210201_P01_WALL-PANEL-ASSY-BACK-LOWER-B1_CAD (Autodesk Fusion 360 design; units mm, degrees)
description: WALL - PANEL ASSY - BACK LOWER - B1 | Vách hậu - cụm tấm dưới trái | P01 | position B1
part number: 210201
description: WALL - PANEL FRAME - BACK LOWER - B1 | Vách hậu - khung dưới trái | P01
part number: 211201
description: WALL - SKIN - BACK LOWER - B1 | Vách hậu - tấm ốp alu dưới trái | P01
part number: 211401
description: WALL - CAVITY FILL - BACK LOWER - B1 | Vách hậu - bông PET dưới trái | P01
part number: 211601
description: HARDWARE - STOP WASHER - Ø10.5 X Ø20 X 1.5 - AL | Long đen chặn nhôm | P01
part number: 831002
description: HARDWARE - RIVET NUT - M6 - SHEREX CAH3-610-4.2 | Tán rút M6 | P01
part number: 838003
description: HARDWARE - LOCATING SPIGOT - M6 X Ø8 - STAINLESS | Chốt định vị Ø8 | P01
part number: 831001
Autodesk Fusion 360 part; units mm, degrees
(part 1 of 2)
ref_plane "WorkPlane1" through (0, 0, 112.26) normal (0, 0, 1) x (1, 0, 0) in component "211201 WALL - PANEL FRAME - BACK LOWER - B1"
sketch "SKETCH - RAIL - BOTTOM TUBE" plane through (0, 0, 112.26) normal (0, 0, 1) x (1, 0, 0) in component "211201 WALL - PANEL FRAME - BACK LOWER - B1"
  line L0 (-1201.74, 804) -> (-2.75, 804)
  line L1 (-2.75, 804) -> (-2.75, 844)
  line L2 (-2.75, 844) -> (-1201.74, 844)
  line L3 (-1201.74, 844) -> (-1201.74, 804)
  dimension "d679" = 1198.99
  dimension "d680" = 40
  dimension "d681" = 1201.74
  dimension "d682" = 804
  constraint horizontal L0
  constraint vertical L1
  constraint horizontal L2
  constraint vertical L3
  measures "d679" horizontal distance of L0.start L0.end
  measures "d680" vertical distance of L0.start L2.end
  measures "d681" horizontal distance of origin L0.start
  measures "d682" vertical distance of origin L0.start
extrude "EXTRUDE - RAIL - BOTTOM TUBE" add sketch "SKETCH - RAIL - BOTTOM TUBE" along normal blind 20 makes body 1 in component "211201 WALL - PANEL FRAME - BACK LOWER - B1"
ref_plane "WorkPlane2" through (0, 0, 113.46) normal (0, 0, 1) x (1, 0, 0) in component "211201 WALL - PANEL FRAME - BACK LOWER - B1"
sketch "SKETCH - RAIL - BOTTOM BORE" plane through (0, 0, 113.46) normal (0, 0, 1) x (1, 0, 0) in component "211201 WALL - PANEL FRAME - BACK LOWER - B1"
  line L0 (-1201.74, 805.2) -> (-2.75, 805.2)
  line L1 (-2.75, 805.2) -> (-2.75, 842.8)
  line L2 (-2.75, 842.8) -> (-1201.74, 842.8)
  line L3 (-1201.74, 842.8) -> (-1201.74, 805.2)
  dimension "d687" = 1198.99
  dimension "d688" = 37.6
  dimension "d689" = 1201.74
  dimension "d690" = 805.2
  constraint horizontal L0
  constraint vertical L1
  constraint horizontal L2
  constraint vertical L3
  measures "d687" horizontal distance of L0.start L0.end
  measures "d688" vertical distance of L0.start L2.end
  measures "d689" horizontal distance of origin L0.start
  measures "d690" vertical distance of origin L0.start
extrude "CUT - RAIL - BOTTOM BORE" cut sketch "SKETCH - RAIL - BOTTOM BORE" along normal blind 17.6 bodies 1 in component "211201 WALL - PANEL FRAME - BACK LOWER - B1"
ref_plane "WorkPlane3" through (0, 0, 1210.87) normal (0, 0, 1) x (1, 0, 0) in component "211201 WALL - PANEL FRAME - BACK LOWER - B1"
sketch "SKETCH - RAIL - TOP TUBE" plane through (0, 0, 1210.87) normal (0, 0, 1) x (1, 0, 0) in component "211201 WALL - PANEL FRAME - BACK LOWER - B1"
  line L0 (-1201.74, 804) -> (-2.75, 804)
  line L1 (-2.75, 804) -> (-2.75, 844)
  line L2 (-2.75, 844) -> (-1201.74, 844)
  line L3 (-1201.74, 844) -> (-1201.74, 804)
  dimension "d695" = 1198.99
  dimension "d696" = 40
  dimension "d697" = 1201.74
  dimension "d698" = 804
  constraint horizontal L0
  constraint vertical L1
  constraint horizontal L2
  constraint vertical L3
  measures "d695" horizontal distance of L0.start L0.end
  measures "d696" vertical distance of L0.start L2.end
  measures "d697" horizontal distance of origin L0.start
  measures "d698" vertical distance of origin L0.start
extrude "EXTRUDE - RAIL - TOP TUBE" add sketch "SKETCH - RAIL - TOP TUBE" along normal blind 20 separate body makes body 2 in component "211201 WALL - PANEL FRAME - BACK LOWER - B1"
ref_plane "WorkPlane4" through (0, 0, 1212.07) normal (0, 0, 1) x (1, 0, 0) in component "211201 WALL - PANEL FRAME - BACK LOWER - B1"
sketch "SKETCH - RAIL - TOP BORE" plane through (0, 0, 1212.07) normal (0, 0, 1) x (1, 0, 0) in component "211201 WALL - PANEL FRAME - BACK LOWER - B1"
  line L0 (-1201.74, 805.2) -> (-2.75, 805.2)
  line L1 (-2.75, 805.2) -> (-2.75, 842.8)
  line L2 (-2.75, 842.8) -> (-1201.74, 842.8)
  line L3 (-1201.74, 842.8) -> (-1201.74, 805.2)
  dimension "d703" = 1198.99
  dimension "d704" = 37.6
  dimension "d705" = 1201.74
  dimension "d706" = 805.2
  constraint horizontal L0
  constraint vertical L1
  constraint horizontal L2
  constraint vertical L3
  measures "d703" horizontal distance of L0.start L0.end
  measures "d704" vertical distance of L0.start L2.end
  measures "d705" horizontal distance of origin L0.start
  measures "d706" vertical distance of origin L0.start
extrude "CUT - RAIL - TOP BORE" cut sketch "SKETCH - RAIL - TOP BORE" along normal blind 17.6 bodies 2 in component "211201 WALL - PANEL FRAME - BACK LOWER - B1"
ref_plane "WorkPlane5" through (0, 0, 132.26) normal (0, 0, 1) x (1, 0, 0) in component "211201 WALL - PANEL FRAME - BACK LOWER - B1"
sketch "SKETCH - STILE - OUTER TUBE" plane through (0, 0, 132.26) normal (0, 0, 1) x (1, 0, 0) in component "211201 WALL - PANEL FRAME - BACK LOWER - B1"
  line L0 (-1201.74, 804) -> (-1181.74, 804)
  line L1 (-1181.74, 804) -> (-1181.74, 844)
  line L2 (-1181.74, 844) -> (-1201.74, 844)
  line L3 (-1201.74, 844) -> (-1201.74, 804)
  dimension "d711" = 20
  dimension "d712" = 40
  dimension "d713" = 1201.74
  dimension "d714" = 804
  constraint horizontal L0
  constraint vertical L1
  constraint horizontal L2
  constraint vertical L3
  measures "d711" horizontal distance of L0.start L0.end
  measures "d712" vertical distance of L0.start L2.end
  measures "d713" horizontal distance of origin L0.start
  measures "d714" vertical distance of origin L0.start
extrude "EXTRUDE - STILE - OUTER TUBE" add sketch "SKETCH - STILE - OUTER TUBE" along normal blind 1078.61 separate body makes body 3 in component "211201 WALL - PANEL FRAME - BACK LOWER - B1"
ref_plane "WorkPlane6" through (0, 0, 132.26) normal (0, 0, 1) x (1, 0, 0) in component "211201 WALL - PANEL FRAME - BACK LOWER - B1"
sketch "SKETCH - STILE - OUTER BORE" plane through (0, 0, 132.26) normal (0, 0, 1) x (1, 0, 0) in component "211201 WALL - PANEL FRAME - BACK LOWER - B1"
  line L0 (-1200.54, 805.2) -> (-1182.94, 805.2)
  line L1 (-1182.94, 805.2) -> (-1182.94, 842.8)
  line L2 (-1182.94, 842.8) -> (-1200.54, 842.8)
  line L3 (-1200.54, 842.8) -> (-1200.54, 805.2)
  dimension "d719" = 17.6
  dimension "d720" = 37.6
  dimension "d721" = 1200.54
  dimension "d722" = 805.2
  constraint horizontal L0
  constraint vertical L1
  constraint horizontal L2
  constraint vertical L3
  measures "d719" horizontal distance of L0.start L0.end
  measures "d720" vertical distance of L0.start L2.end
  measures "d721" horizontal distance of origin L0.start
  measures "d722" vertical distance of origin L0.start
extrude "CUT - STILE - OUTER BORE" cut sketch "SKETCH - STILE - OUTER BORE" along normal blind 1078.61 bodies 3 in component "211201 WALL - PANEL FRAME - BACK LOWER - B1"
ref_plane "WorkPlane7" through (0, 0, 132.26) normal (0, 0, 1) x (1, 0, 0) in component "211201 WALL - PANEL FRAME - BACK LOWER - B1"
sketch "SKETCH - STILE - CENTRE TUBE" plane through (0, 0, 132.26) normal (0, 0, 1) x (1, 0, 0) in component "211201 WALL - PANEL FRAME - BACK LOWER - B1"
  line L0 (-22.75, 804) -> (-2.75, 804)
  line L1 (-2.75, 804) -> (-2.75, 844)
  line L2 (-2.75, 844) -> (-22.75, 844)
  line L3 (-22.75, 844) -> (-22.75, 804)
  dimension "d727" = 20
  dimension "d728" = 40
  dimension "d729" = 22.75
  dimension "d730" = 804
  constraint horizontal L0
  constraint vertical L1
  constraint horizontal L2
  constraint vertical L3
  measures "d727" horizontal distance of L0.start L0.end
  measures "d728" vertical distance of L0.start L2.end
  measures "d729" horizontal distance of origin L0.start
  measures "d730" vertical distance of origin L0.start
extrude "EXTRUDE - STILE - CENTRE TUBE" add sketch "SKETCH - STILE - CENTRE TUBE" along normal blind 1078.61 separate body makes body 4 in component "211201 WALL - PANEL FRAME - BACK LOWER - B1"
ref_plane "WorkPlane8" through (0, 0, 132.26) normal (0, 0, 1) x (1, 0, 0) in component "211201 WALL - PANEL FRAME - BACK LOWER - B1"
sketch "SKETCH - STILE - CENTRE BORE" plane through (0, 0, 132.26) normal (0, 0, 1) x (1, 0, 0) in component "211201 WALL - PANEL FRAME - BACK LOWER - B1"
  line L0 (-21.55, 805.2) -> (-3.95, 805.2)
  line L1 (-3.95, 805.2) -> (-3.95, 842.8)
  line L2 (-3.95, 842.8) -> (-21.55, 842.8)
  line L3 (-21.55, 842.8) -> (-21.55, 805.2)
  dimension "d735" = 17.6
  dimension "d736" = 37.6
  dimension "d737" = 21.55
  dimension "d738" = 805.2
  constraint horizontal L0
  constraint vertical L1
  constraint horizontal L2
  constraint vertical L3
  measures "d735" horizontal distance of L0.start L0.end
  measures "d736" vertical distance of L0.start L2.end
  measures "d737" horizontal distance of origin L0.start
  measures "d738" vertical distance of origin L0.start
extrude "CUT - STILE - CENTRE BORE" cut sketch "SKETCH - STILE - CENTRE BORE" along normal blind 1078.61 bodies 4 in component "211201 WALL - PANEL FRAME - BACK LOWER - B1"
ref_plane "WorkPlane9" through (0, 0, 132.26) normal (0, 0, 1) x (1, 0, 0) in component "211201 WALL - PANEL FRAME - BACK LOWER - B1"
sketch "SKETCH - STILE - MID 1 TUBE" plane through (0, 0, 132.26) normal (0, 0, 1) x (1, 0, 0) in component "211201 WALL - PANEL FRAME - BACK LOWER - B1"
  line L0 (-808.7433, 804) -> (-788.7433, 804)
  line L1 (-788.7433, 804) -> (-788.7433, 844)
  line L2 (-788.7433, 844) -> (-808.7433, 844)
  line L3 (-808.7433, 844) -> (-808.7433, 804)
  dimension "d743" = 20
  dimension "d744" = 40
  dimension "d745" = 808.7433
  dimension "d746" = 804
  constraint horizontal L0
  constraint vertical L1
  constraint horizontal L2
  constraint vertical L3
  measures "d743" horizontal distance of L0.start L0.end
  measures "d744" vertical distance of L0.start L2.end
  measures "d745" horizontal distance of origin L0.start
  measures "d746" vertical distance of origin L0.start
extrude "EXTRUDE - STILE - MID 1 TUBE" add sketch "SKETCH - STILE - MID 1 TUBE" along normal blind 1078.61 separate body makes body 5 in component "211201 WALL - PANEL FRAME - BACK LOWER - B1"
ref_plane "WorkPlane10" through (0, 0, 132.26) normal (0, 0, 1) x (1, 0, 0) in component "211201 WALL - PANEL FRAME - BACK LOWER - B1"
sketch "SKETCH - STILE - MID 1 BORE" plane through (0, 0, 132.26) normal (0, 0, 1) x (1, 0, 0) in component "211201 WALL - PANEL FRAME - BACK LOWER - B1"
  line L0 (-807.7433, 805) -> (-789.7433, 805)
  line L1 (-789.7433, 805) -> (-789.7433, 843)
  line L2 (-789.7433, 843) -> (-807.7433, 843)
  line L3 (-807.7433, 843) -> (-807.7433, 805)
  dimension "d751" = 18
  dimension "d752" = 38
  dimension "d753" = 807.7433
  dimension "d754" = 805
  constraint horizontal L0
  constraint vertical L1
  constraint horizontal L2
  constraint vertical L3
  measures "d751" horizontal distance of L0.start L0.end
  measures "d752" vertical distance of L0.start L2.end
  measures "d753" horizontal distance of origin L0.start
  measures "d754" vertical distance of origin L0.start
extrude "CUT - STILE - MID 1 BORE" cut sketch "SKETCH - STILE - MID 1 BORE" along normal blind 1078.61 bodies 5 in component "211201 WALL - PANEL FRAME - BACK LOWER - B1"
pattern_linear "PATTERN - STILES - MID" count 2 spacing 392.9967 along (1, 0, 0) of bodies 5 makes body 6 in component "211201 WALL - PANEL FRAME - BACK LOWER - B1"
ref_plane "WorkPlane1" through (0, 0, 112.26) normal (0, 0, 1) x (1, 0, 0) in component "211401 WALL - SKIN - BACK LOWER - B1"
sketch "SKETCH - SKIN PLATE" plane through (0, 0, 112.26) normal (0, 0, 1) x (1, 0, 0) in component "211401 WALL - SKIN - BACK LOWER - B1"
  line L0 (-1201.74, 847) -> (-1.13, 847)
  line L1 (-1.13, 847) -> (-1.13, 850)
  line L2 (-1.13, 850) -> (-1201.74, 850)
  line L3 (-1201.74, 850) -> (-1201.74, 847)
  dimension "d763" = 1200.61
  dimension "d764" = 3
  dimension "d765" = 1201.74
  dimension "d766" = 847
  constraint horizontal L0
  constraint vertical L1
  constraint horizontal L2
  constraint vertical L3
  measures "d763" horizontal distance of L0.start L0.end
  measures "d764" vertical distance of L0.start L2.end
  measures "d765" horizontal distance of origin L0.start
  measures "d766" vertical distance of origin L0.start
extrude "EXTRUDE - SKIN PLATE" add sketch "SKETCH - SKIN PLATE" along normal blind 1118.61 separate body makes body 7 in component "211401 WALL - SKIN - BACK LOWER - B1"
ref_plane "WorkPlane1" through (0, 0, 132.26) normal (0, 0, 1) x (1, 0, 0) in component "211601 WALL - CAVITY FILL - BACK LOWER - B1"
sketch "SKETCH - FILL BAY 1" plane through (0, 0, 132.26) normal (0, 0, 1) x (1, 0, 0) in component "211601 WALL - CAVITY FILL - BACK LOWER - B1"
  line L0 (-1181.74, 804) -> (-808.7433, 804)
  line L1 (-808.7433, 804) -> (-808.7433, 844)
  line L2 (-808.7433, 844) -> (-1181.74, 844)
  line L3 (-1181.74, 844) -> (-1181.74, 804)
  dimension "d771" = 372.9967
  dimension "d772" = 40
  dimension "d773" = 1181.74
  dimension "d774" = 804
  constraint horizontal L0
  constraint vertical L1
  constraint horizontal L2
  constraint vertical L3
  measures "d771" horizontal distance of L0.start L0.end
  measures "d772" vertical distance of L0.start L2.end
  measures "d773" horizontal distance of origin L0.start
  measures "d774" vertical distance of origin L0.start
extrude "EXTRUDE - FILL BAY 1" add sketch "SKETCH - FILL BAY 1" along normal blind 1078.61 separate body makes body 8 in component "211601 WALL - CAVITY FILL - BACK LOWER - B1"
pattern_linear "PATTERN - FILL BAYS" count 3 spacing 392.9967 along (1, 0, 0) of bodies 8 makes body 9 at (-540.0789, 844, 851.3333) makes body 10 at (-147.0822, 844, 491.7967) in component "211601 WALL - CAVITY FILL - BACK LOWER - B1"
ref_plane "WorkPlane2" through (0, 0, 132.26) normal (0, 0, 1) x (1, 0, 0) in component "211601 WALL - CAVITY FILL - BACK LOWER - B1"
sketch "SKETCH - FILL POCKET BOTTOM BOLT 1" plane through (0, 0, 132.26) normal (0, 0, 1) x (1, 0, 0) in component "211601 WALL - CAVITY FILL - BACK LOWER - B1"
  line L0 (-1011.74, 804) -> (-951.74, 804)
  line L1 (-951.74, 804) -> (-951.74, 844)
  line L2 (-951.74, 844) -> (-1011.74, 844)
  line L3 (-1011.74, 844) -> (-1011.74, 804)
  dimension "d783" = 60
  dimension "d784" = 40
  dimension "d785" = 1011.74
  dimension "d786" = 804
  constraint horizontal L0
  constraint vertical L1
  constraint horizontal L2
  constraint vertical L3
  measures "d783" horizontal distance of L0.start L0.end
  measures "d784" vertical distance of L0.start L2.end
  measures "d785" horizontal distance of origin L0.start
  measures "d786" vertical distance of origin L0.start
extrude "CUT - FILL POCKET BOTTOM BOLT 1" cut sketch "SKETCH - FILL POCKET BOTTOM BOLT 1" along normal blind 60 bodies 8 in component "211601 WALL - CAVITY FILL - BACK LOWER - B1"
ref_plane "WorkPlane3" through (0, 0, 132.26) normal (0, 0, 1) x (1, 0, 0) in component "211601 WALL - CAVITY FILL - BACK LOWER - B1"
sketch "SKETCH - FILL POCKET BOTTOM BOLT 2" plane through (0, 0, 132.26) normal (0, 0, 1) x (1, 0, 0) in component "211601 WALL - CAVITY FILL - BACK LOWER - B1"
  line L0 (-758.7433, 804) -> (-698.7433, 804)
  line L1 (-698.7433, 804) -> (-698.7433, 844)
  line L2 (-698.7433, 844) -> (-758.7433, 844)
  line L3 (-758.7433, 844) -> (-758.7433, 804)
  dimension "d791" = 60
  dimension "d792" = 40
  dimension "d793" = 758.7433
  dimension "d794" = 804
  constraint horizontal L0
  constraint vertical L1
  constraint horizontal L2
  constraint vertical L3
  measures "d791" horizontal distance of L0.start L0.end
  measures "d792" vertical distance of L0.start L2.end
  measures "d793" horizontal distance of origin L0.start
  measures "d794" vertical distance of origin L0.start
extrude "CUT - FILL POCKET BOTTOM BOLT 2" cut sketch "SKETCH - FILL POCKET BOTTOM BOLT 2" along normal blind 60 bodies 9 in component "211601 WALL - CAVITY FILL - BACK LOWER - B1"
ref_plane "WorkPlane4" through (0, 0, 132.26) normal (0, 0, 1) x (1, 0, 0) in component "211601 WALL - CAVITY FILL - BACK LOWER - B1"
sketch "SKETCH - FILL POCKET BOTTOM BOLT 3" plane through (0, 0, 132.26) normal (0, 0, 1) x (1, 0, 0) in component "211601 WALL - CAVITY FILL - BACK LOWER - B1"
  line L0 (-505.7467, 804) -> (-445.7467, 804)
  line L1 (-445.7467, 804) -> (-445.7467, 844)
  line L2 (-445.7467, 844) -> (-505.7467, 844)
  line L3 (-505.7467, 844) -> (-505.7467, 804)
  dimension "d799" = 60
  dimension "d800" = 40
  dimension "d801" = 505.7467
  dimension "d802" = 804
  constraint horizontal L0
  constraint vertical L1
  constraint horizontal L2
  constraint vertical L3
  measures "d799" horizontal distance of L0.start L0.end
  measures "d800" vertical distance of L0.start L2.end
  measures "d801" horizontal distance of origin L0.start
  measures "d802" vertical distance of origin L0.start
extrude "CUT - FILL POCKET BOTTOM BOLT 3" cut sketch "SKETCH - FILL POCKET BOTTOM BOLT 3" along normal blind 60 bodies 9 in component "211601 WALL - CAVITY FILL - BACK LOWER - B1"
ref_plane "WorkPlane5" through (0, 0, 132.26) normal (0, 0, 1) x (1, 0, 0) in component "211601 WALL - CAVITY FILL - BACK LOWER - B1"
sketch "SKETCH - FILL POCKET BOTTOM BOLT 4" plane through (0, 0, 132.26) normal (0, 0, 1) x (1, 0, 0) in component "211601 WALL - CAVITY FILL - BACK LOWER - B1"
  line L0 (-252.75, 804) -> (-192.75, 804)
  line L1 (-192.75, 804) -> (-192.75, 844)
  line L2 (-192.75, 844) -> (-252.75, 844)
  line L3 (-252.75, 844) -> (-252.75, 804)
  dimension "d807" = 60
  dimension "d808" = 40
  dimension "d809" = 252.75
  dimension "d810" = 804
  constraint horizontal L0
  constraint vertical L1
  constraint horizontal L2
  constraint vertical L3
  measures "d807" horizontal distance of L0.start L0.end
  measures "d808" vertical distance of L0.start L2.end
  measures "d809" horizontal distance of origin L0.start
  measures "d810" vertical distance of origin L0.start
extrude "CUT - FILL POCKET BOTTOM BOLT 4" cut sketch "SKETCH - FILL POCKET BOTTOM BOLT 4" along normal blind 60 bodies 10 in component "211601 WALL - CAVITY FILL - BACK LOWER - B1"
ref_plane "WorkPlane6" through (0, 0, 302.26) normal (0, 0, 1) x (1, 0, 0) in component "211601 WALL - CAVITY FILL - BACK LOWER - B1"
sketch "SKETCH - FILL POCKET CORNER BOLT 1" plane through (0, 0, 302.26) normal (0, 0, 1) x (1, 0, 0) in component "211601 WALL - CAVITY FILL - BACK LOWER - B1"
  line L0 (-1181.74, 804) -> (-1121.74, 804)
  line L1 (-1121.74, 804) -> (-1121.74, 844)
  line L2 (-1121.74, 844) -> (-1181.74, 844)
  line L3 (-1181.74, 844) -> (-1181.74, 804)
  dimension "d815" = 60
  dimension "d816" = 40
  dimension "d817" = 1181.74
  dimension "d818" = 804
  constraint horizontal L0
  constraint vertical L1
  constraint horizontal L2
  constraint vertical L3
  measures "d815" horizontal distance of L0.start L0.end
  measures "d816" vertical distance of L0.start L2.end
  measures "d817" horizontal distance of origin L0.start
  measures "d818" vertical distance of origin L0.start
extrude "CUT - FILL POCKET CORNER BOLT 1" cut sketch "SKETCH - FILL POCKET CORNER BOLT 1" along normal blind 60 bodies 8 in component "211601 WALL - CAVITY FILL - BACK LOWER - B1"
ref_plane "WorkPlane7" through (0, 0, 641.565) normal (0, 0, 1) x (1, 0, 0) in component "211601 WALL - CAVITY FILL - BACK LOWER - B1"
sketch "SKETCH - FILL POCKET CORNER BOLT 2" plane through (0, 0, 641.565) normal (0, 0, 1) x (1, 0, 0) in component "211601 WALL - CAVITY FILL - BACK LOWER - B1"
  line L0 (-1181.74, 804) -> (-1121.74, 804)
  line L1 (-1121.74, 804) -> (-1121.74, 844)
  line L2 (-1121.74, 844) -> (-1181.74, 844)
  line L3 (-1181.74, 844) -> (-1181.74, 804)
  dimension "d823" = 60
  dimension "d824" = 40
  dimension "d825" = 1181.74
  dimension "d826" = 804
  constraint horizontal L0
  constraint vertical L1
  constraint horizontal L2
  constraint vertical L3
  measures "d823" horizontal distance of L0.start L0.end
  measures "d824" vertical distance of L0.start L2.end
  measures "d825" horizontal distance of origin L0.start
  measures "d826" vertical distance of origin L0.start
extrude "CUT - FILL POCKET CORNER BOLT 2" cut sketch "SKETCH - FILL POCKET CORNER BOLT 2" along normal blind 60 bodies 8 in component "211601 WALL - CAVITY FILL - BACK LOWER - B1"
ref_plane "WorkPlane8" through (0, 0, 980.87) normal (0, 0, 1) x (1, 0, 0) in component "211601 WALL - CAVITY FILL - BACK LOWER - B1"
sketch "SKETCH - FILL POCKET CORNER BOLT 3" plane through (0, 0, 980.87) normal (0, 0, 1) x (1, 0, 0) in component "211601 WALL - CAVITY FILL - BACK LOWER - B1"
  line L0 (-1181.74, 804) -> (-1121.74, 804)
  line L1 (-1121.74, 804) -> (-1121.74, 844)
  line L2 (-1121.74, 844) -> (-1181.74, 844)
  line L3 (-1181.74, 844) -> (-1181.74, 804)
  dimension "d831" = 60
  dimension "d832" = 40
  dimension "d833" = 1181.74
  dimension "d834" = 804
  constraint horizontal L0
  constraint vertical L1
  constraint horizontal L2
  constraint vertical L3
  measures "d831" horizontal distance of L0.start L0.end
  measures "d832" vertical distance of L0.start L2.end
  measures "d833" horizontal distance of origin L0.start
  measures "d834" vertical distance of origin L0.start
extrude "CUT - FILL POCKET CORNER BOLT 3" cut sketch "SKETCH - FILL POCKET CORNER BOLT 3" along normal blind 60 bodies 8 in component "211601 WALL - CAVITY FILL - BACK LOWER - B1"
ref_plane "WorkPlane11" through (0, 0, 112.26) normal (0, 0, 1) x (1, 0, 0) in component "211201 WALL - PANEL FRAME - BACK LOWER - B1"
sketch "HOLE CENTRE - BOTTOM RAIL BOLT CLEARANCE 1" plane through (0, 0, 112.26) normal (0, 0, 1) x (1, 0, 0) in component "211201 WALL - PANEL FRAME - BACK LOWER - B1"
  point P0 (-981.74, 824)
  dimension "d839" = 981.74
  dimension "d840" = 824
  measures "d839" horizontal distance of origin P0
  measures "d840" vertical distance of origin P0
hole "HOLE - BOTTOM RAIL BOLT CLEARANCE 1" at (-981.74, 824, 112.26) direction (0, 0, 1) diameter 7 depth 1.2 tip angle 118 bodies 1 in component "211201 WALL - PANEL FRAME - BACK LOWER - B1"
ref_plane "WorkPlane12" through (0, 0, 132.26) normal (0, 0, 1) x (1, 0, 0) in component "211201 WALL - PANEL FRAME - BACK LOWER - B1"
sketch "HOLE CENTRE - BOTTOM RAIL KEY ACCESS 1" plane through (0, 0, 132.26) normal (0, 0, 1) x (1, 0, 0) in component "211201 WALL - PANEL FRAME - BACK LOWER - B1"
  point P0 (-981.74, 824)
  dimension "d846" = 981.74
  dimension "d847" = 824
  measures "d846" horizontal distance of origin P0
  measures "d847" vertical distance of origin P0
hole "HOLE - BOTTOM RAIL KEY ACCESS 1" at (-981.74, 824, 132.26) direction (0, 0, -1) diameter 19 depth 1.2 tip angle 118 bodies 1 in component "211201 WALL - PANEL FRAME - BACK LOWER - B1"
pattern_linear "PATTERN - BOTTOM RAIL BOLT HOLES" count 4 spacing 252.9967 along (1, 0, 0) of "HOLE - BOTTOM RAIL BOLT CLEARANCE 1", "HOLE - BOTTOM RAIL KEY ACCESS 1" in component "211201 WALL - PANEL FRAME - BACK LOWER - B1"
ref_plane "WorkPlane13" through (0, 0, 112.26) normal (0, 0, 1) x (1, 0, 0) in component "211201 WALL - PANEL FRAME - BACK LOWER - B1"
sketch "HOLE CENTRE - BOTTOM RAIL SPIGOT ROUND" plane through (0, 0, 112.26) normal (0, 0, 1) x (1, 0, 0) in component "211201 WALL - PANEL FRAME - BACK LOWER - B1"
  point P0 (-102.75, 824)
  dimension "d857" = 102.75
  dimension "d858" = 824
  measures "d857" horizontal distance of origin P0
  measures "d858" vertical distance of origin P0
hole "HOLE - BOTTOM RAIL SPIGOT ROUND" at (-102.75, 824, 112.26) direction (0, 0, 1) diameter 8.5 depth 1.2 tip angle 118 bodies 1 in component "211201 WALL - PANEL FRAME - BACK LOWER - B1"
ref_plane "WorkPlane14" through (0, 0, 112.26) normal (0, 0, 1) x (1, 0, 0) in component "211201 WALL - PANEL FRAME - BACK LOWER - B1"
sketch "SKETCH - BOTTOM RAIL SPIGOT SLOT" plane through (0, 0, 112.26) normal (0, 0, 1) x (1, 0, 0) in component "211201 WALL - PANEL FRAME - BACK LOWER - B1"
  line L0 (-1104.49, 819.75) -> (-1098.99, 819.75)
  line L1 (-1098.99, 819.75) -> (-1098.99, 828.25)
  line L2 (-1098.99, 828.25) -> (-1104.49, 828.25)
  line L3 (-1104.49, 828.25) -> (-1104.49, 819.75)
  dimension "d864" = 5.5
  dimension "d865" = 8.5
  dimension "d866" = 1104.49
  dimension "d867" = 819.75
  constraint horizontal L0
  constraint vertical L1
  constraint horizontal L2
  constraint vertical L3
  measures "d864" horizontal distance of L0.start L0.end
  measures "d865" vertical distance of L0.start L2.end
  measures "d866" horizontal distance of origin L0.start
  measures "d867" vertical distance of origin L0.start
extrude "CUT - BOTTOM RAIL SPIGOT SLOT" cut sketch "SKETCH - BOTTOM RAIL SPIGOT SLOT" along normal blind 1.2 bodies 1 in component "211201 WALL - PANEL FRAME - BACK LOWER - B1"
ref_plane "WorkPlane15" through (0, 0, 112.26) normal (0, 0, 1) x (1, 0, 0) in component "211201 WALL - PANEL FRAME - BACK LOWER - B1"
sketch "HOLE CENTRE - BOTTOM RAIL SPIGOT SLOT END 1" plane through (0, 0, 112.26) normal (0, 0, 1) x (1, 0, 0) in component "211201 WALL - PANEL FRAME - BACK LOWER - B1"
  point P0 (-1104.49, 824)
  dimension "d872" = 1104.49
  dimension "d873" = 824
  measures "d872" horizontal distance of origin P0
  measures "d873" vertical distance of origin P0
hole "HOLE - BOTTOM RAIL SPIGOT SLOT END 1" at (-1104.49, 824, 112.26) direction (0, 0, 1) diameter 8.5 depth 1.2 tip angle 118 bodies 1 in component "211201 WALL - PANEL FRAME - BACK LOWER - B1"
ref_plane "WorkPlane16" through (0, 0, 112.26) normal (0, 0, 1) x (1, 0, 0) in component "211201 WALL - PANEL FRAME - BACK LOWER - B1"
sketch "HOLE CENTRE - BOTTOM RAIL SPIGOT SLOT END 2" plane through (0, 0, 112.26) normal (0, 0, 1) x (1, 0, 0) in component "211201 WALL - PANEL FRAME - BACK LOWER - B1"
  point P0 (-1098.99, 824)
  dimension "d879" = 1098.99
  dimension "d880" = 824
  measures "d879" horizontal distance of origin P0
  measures "d880" vertical distance of origin P0
hole "HOLE - BOTTOM RAIL SPIGOT SLOT END 2" at (-1098.99, 824, 112.26) direction (0, 0, 1) diameter 8.5 depth 1.2 tip angle 118 bodies 1 in component "211201 WALL - PANEL FRAME - BACK LOWER - B1"
ref_plane "WorkPlane17" through (0, 0, 1230.87) normal (0, 0, 1) x (1, 0, 0) in component "211201 WALL - PANEL FRAME - BACK LOWER - B1"
sketch "HOLE CENTRE - TOP RAIL RIVNUT 1" plane through (0, 0, 1230.87) normal (0, 0, 1) x (1, 0, 0) in component "211201 WALL - PANEL FRAME - BACK LOWER - B1"
  point P0 (-981.74, 824)
  dimension "d886" = 981.74
  dimension "d887" = 824
  measures "d886" horizontal distance of origin P0
  measures "d887" vertical distance of origin P0
hole "HOLE - TOP RAIL RIVNUT 1" at (-981.74, 824, 1230.87) direction (0, 0, -1) diameter 9.53 depth 1.2 tip angle 118 bodies 2 in component "211201 WALL - PANEL FRAME - BACK LOWER - B1"
pattern_linear "PATTERN - TOP RAIL RIVNUTS" count 4 spacing 252.9967 along (1, 0, 0) of "HOLE - TOP RAIL RIVNUT 1" in component "211201 WALL - PANEL FRAME - BACK LOWER - B1"
ref_plane "WorkPlane18" through (0, 0, 1230.87) normal (0, 0, 1) x (1, 0, 0) in component "211201 WALL - PANEL FRAME - BACK LOWER - B1"
sketch "HOLE CENTRE - TOP RAIL SPIGOT RIVNUT LOW X" plane through (0, 0, 1230.87) normal (0, 0, 1) x (1, 0, 0) in component "211201 WALL - PANEL FRAME - BACK LOWER - B1"
  point P0 (-1101.74, 824)
  dimension "d897" = 1101.74
  dimension "d898" = 824
  measures "d897" horizontal distance of origin P0
  measures "d898" vertical distance of origin P0
hole "HOLE - TOP RAIL SPIGOT RIVNUT LOW X" at (-1101.74, 824, 1230.87) direction (0, 0, -1) diameter 9.53 depth 1.2 tip angle 118 bodies 2 in component "211201 WALL - PANEL FRAME - BACK LOWER - B1"
ref_plane "WorkPlane19" through (0, 0, 1230.87) normal (0, 0, 1) x (1, 0, 0) in component "211201 WALL - PANEL FRAME - BACK LOWER - B1"
sketch "HOLE CENTRE - TOP RAIL SPIGOT RIVNUT HIGH X" plane through (0, 0, 1230.87) normal (0, 0, 1) x (1, 0, 0) in component "211201 WALL - PANEL FRAME - BACK LOWER - B1"
  point P0 (-102.75, 824)
  dimension "d904" = 102.75
  dimension "d905" = 824
  measures "d904" horizontal distance of origin P0
  measures "d905" vertical distance of origin P0
hole "HOLE - TOP RAIL SPIGOT RIVNUT HIGH X" at (-102.75, 824, 1230.87) direction (0, 0, -1) diameter 9.53 depth 1.2 tip angle 118 bodies 2 in component "211201 WALL - PANEL FRAME - BACK LOWER - B1"
ref_plane "WorkPlane20" through (-1201.74, 0, 0) normal (1, 0, 0) x (0, 1, 0) in component "211201 WALL - PANEL FRAME - BACK LOWER - B1"
sketch "HOLE CENTRE - OUTER STILE CORNER BOLT CLEARANCE 1" plane through (-1201.74, 0, 0) normal (1, 0, 0) x (0, 0, -1) in component "211201 WALL - PANEL FRAME - BACK LOWER - B1"
  point P0 (-332.26, 824)
  dimension "d911" = 824
  dimension "d912" = 332.26
  measures "d911" vertical distance of origin P0
  measures "d912" horizontal distance of origin P0
hole "HOLE - OUTER STILE CORNER BOLT CLEARANCE 1" at (-1201.74, 824, 332.26) direction (1, 0, 0) diameter 7 depth 1.2 tip angle 118 bodies 3 in component "211201 WALL - PANEL FRAME - BACK LOWER - B1"
ref_plane "WorkPlane21" through (-1181.74, 0, 0) normal (1, 0, 0) x (0, 1, 0) in component "211201 WALL - PANEL FRAME - BACK LOWER - B1"
sketch "HOLE CENTRE - OUTER STILE CORNER KEY ACCESS 1" plane through (-1181.74, 0, 0) normal (1, 0, 0) x (0, 0, -1) in component "211201 WALL - PANEL FRAME - BACK LOWER - B1"
  point P0 (-332.26, 824)
  dimension "d918" = 824
  dimension "d919" = 332.26
  measures "d918" vertical distance of origin P0
  measures "d919" horizontal distance of origin P0
hole "HOLE - OUTER STILE CORNER KEY ACCESS 1" at (-1181.74, 824, 332.26) direction (-1, 0, 0) diameter 19 depth 1.2 tip angle 118 bodies 3 in component "211201 WALL - PANEL FRAME - BACK LOWER - B1"
pattern_linear "PATTERN - OUTER STILE CORNER BOLT HOLES" count 3 spacing 339.305 along (0, 0, 1) of "HOLE - OUTER STILE CORNER BOLT CLEARANCE 1", "HOLE - OUTER STILE CORNER KEY ACCESS 1" in component "211201 WALL - PANEL FRAME - BACK LOWER - B1"
ref_plane "WorkPlane22" through (-2.75, 0, 0) normal (1, 0, 0) x (0, 1, 0) in component "211201 WALL - PANEL FRAME - BACK LOWER - B1"
sketch "HOLE CENTRE - CENTRE STILE PIN HOLE 1" plane through (-2.75, 0, 0) normal (1, 0, 0) x (0, 0, -1) in component "211201 WALL - PANEL FRAME - BACK LOWER - B1"
  point P0 (-332.26, 824)
  dimension "d929" = 824
  dimension "d930" = 332.26
  measures "d929" vertical distance of origin P0
  measures "d930" horizontal distance of origin P0
hole "HOLE - CENTRE STILE PIN HOLE 1" at (-2.75, 824, 332.26) direction (-1, 0, 0) diameter 7 depth 1.2 tip angle 118 bodies 4 in component "211201 WALL - PANEL FRAME - BACK LOWER - B1"
pattern_linear "PATTERN - CENTRE STILE PIN HOLES" count 3 spacing 339.305 along (0, 0, 1) of "HOLE - CENTRE STILE PIN HOLE 1" in component "211201 WALL - PANEL FRAME - BACK LOWER - B1"
chamfer "CHAMFER - CLOSING SEAM LEAD-IN (R-J9)" distance 1 angle 45 1 edges at (-2.75, 824, 1230.87) tangent chain off on bodies 2 in component "211201 WALL - PANEL FRAME - BACK LOWER - B1"
ref_plane "WorkPlane1" through (0, 0, 1230.87) normal (0, 0, 1) x (1, 0, 0) in component "831002 HARDWARE - STOP WASHER - Ø10.5 X Ø20 X 1.5 - AL"
sketch "SKETCH - STOP WASHER TOP RAIL" plane through (0, 0, 1230.87) normal (0, 0, 1) x (1, 0, 0) in component "831002 HARDWARE - STOP WASHER - Ø10.5 X Ø20 X 1.5 - AL"
  circle A0 centre (-981.74, 824) radius 10
  circle A1 centre (-981.74, 824) radius 5.25
  dimension "d941" = 981.74
  dimension "d942" = 824
  dimension "d943" = 20
  dimension "d944" = 10.5
  measures "d941" horizontal distance of origin A0.centre
  measures "d942" vertical distance of origin A0.centre
  measures "d943" diameter of A0
  measures "d944" diameter of A1
extrude "EXTRUDE - STOP WASHER TOP RAIL" add sketch "SKETCH - STOP WASHER TOP RAIL" along normal blind 1.5 separate body makes body 11 in component "831002 HARDWARE - STOP WASHER - Ø10.5 X Ø20 X 1.5 - AL"
ref_plane "WorkPlane1" through (0, 0, 1232.37) normal (0, 0, 1) x (1, 0, 0) in component "838003 HARDWARE - RIVET NUT - M6 - SHEREX CAH3-610-4.2"
sketch "SKETCH - RIVNUT HEAD TOP RAIL" plane through (0, 0, 1232.37) normal (0, 0, 1) x (1, 0, 0) in component "838003 HARDWARE - RIVET NUT - M6 - SHEREX CAH3-610-4.2"
  circle A0 centre (-981.74, 824) radius 6.48
  circle A1 centre (-981.74, 824) radius 3
  dimension "d949" = 981.74
  dimension "d950" = 824
  dimension "d951" = 12.96
  dimension "d952" = 6
  measures "d949" horizontal distance of origin A0.centre
  measures "d950" vertical distance of origin A0.centre
  measures "d951" diameter of A0
  measures "d952" diameter of A1
extrude "EXTRUDE - RIVNUT HEAD TOP RAIL" add sketch "SKETCH - RIVNUT HEAD TOP RAIL" along normal blind 0.76 separate body makes body 12 in component "838003 HARDWARE - RIVET NUT - M6 - SHEREX CAH3-610-4.2"
ref_plane "WorkPlane2" through (0, 0, 1232.37) normal (0, 0, 1) x (1, 0, 0) in component "838003 HARDWARE - RIVET NUT - M6 - SHEREX CAH3-610-4.2"
sketch "SKETCH - RIVNUT BODY TOP RAIL" plane through (0, 0, 1232.37) normal (0, 0, 1) x (1, 0, 0) in component "838003 HARDWARE - RIVET NUT - M6 - SHEREX CAH3-610-4.2"
  circle A0 centre (-981.74, 824) radius 4.75
  circle A1 centre (-981.74, 824) radius 3
  dimension "d957" = 981.74
  dimension "d958" = 824
  dimension "d959" = 9.5
  dimension "d960" = 6
  measures "d957" horizontal distance of origin A0.centre
  measures "d958" vertical distance of origin A0.centre
  measures "d959" diameter of A0
  measures "d960" diameter of A1
extrude "EXTRUDE - RIVNUT BODY TOP RAIL" add sketch "SKETCH - RIVNUT BODY TOP RAIL" against normal blind 10.16 separate body makes body 13 in component "838003 HARDWARE - RIVET NUT - M6 - SHEREX CAH3-610-4.2"
combine "COMBINE - RIVNUT TOP RAIL" operation add target body 12 tool bodies 13 in component "838003 HARDWARE - RIVET NUT - M6 - SHEREX CAH3-610-4.2"
pattern_linear "PATTERN - STOP WASHER - TOP RAIL" count 4 spacing 252.9967 along (1, 0, 0) of bodies 11 makes body 14 at (-726.3944, 832.0588, 1230.87) makes body 15 at (-467.5931, 822.0049, 1230.87) makes body 16 at (-214.5964, 822.0049, 1230.87) in component "831002 HARDWARE - STOP WASHER - Ø10.5 X Ø20 X 1.5 - AL"
pattern_linear "PATTERN - RIVNUT - TOP RAIL" count 4 spacing 252.9967 along (1, 0, 0) of bodies 12 makes body 17 at (-727.9185, 828.6778, 1225.5967) makes body 18 at (-472.43, 827.4004, 1225.5967) makes body 19 at (-219.4334, 827.4004, 1225.5967) in component "838003 HARDWARE - RIVET NUT - M6 - SHEREX CAH3-610-4.2"
ref_plane "WorkPlane3" through (0, 0, 1230.87) normal (0, 0, 1) x (1, 0, 0) in component "838003 HARDWARE - RIVET NUT - M6 - SHEREX CAH3-610-4.2"
sketch "SKETCH - RIVNUT HEAD TOP RAIL SPIGOT LOW X" plane through (0, 0, 1230.87) normal (0, 0, 1) x (1, 0, 0) in component "838003 HARDWARE - RIVET NUT - M6 - SHEREX CAH3-610-4.2"
  circle A0 centre (-1101.74, 824) radius 6.48
  circle A1 centre (-1101.74, 824) radius 3
  dimension "d975" = 1101.74
  dimension "d976" = 824
  dimension "d977" = 12.96
  dimension "d978" = 6
  measures "d975" horizontal distance of origin A0.centre
  measures "d976" vertical distance of origin A0.centre
  measures "d977" diameter of A0
  measures "d978" diameter of A1
extrude "EXTRUDE - RIVNUT HEAD TOP RAIL SPIGOT LOW X" add sketch "SKETCH - RIVNUT HEAD TOP RAIL SPIGOT LOW X" along normal blind 0.76 separate body makes body 20 in component "838003 HARDWARE - RIVET NUT - M6 - SHEREX CAH3-610-4.2"
ref_plane "WorkPlane4" through (0, 0, 1230.87) normal (0, 0, 1) x (1, 0, 0) in component "838003 HARDWARE - RIVET NUT - M6 - SHEREX CAH3-610-4.2"
sketch "SKETCH - RIVNUT BODY TOP RAIL SPIGOT LOW X" plane through (0, 0, 1230.87) normal (0, 0, 1) x (1, 0, 0) in component "838003 HARDWARE - RIVET NUT - M6 - SHEREX CAH3-610-4.2"
  circle A0 centre (-1101.74, 824) radius 4.75
  circle A1 centre (-1101.74, 824) radius 3
  dimension "d983" = 1101.74
  dimension "d984" = 824
  dimension "d985" = 9.5
  dimension "d986" = 6
  measures "d983" horizontal distance of origin A0.centre
  measures "d984" vertical distance of origin A0.centre
  measures "d985" diameter of A0
  measures "d986" diameter of A1
extrude "EXTRUDE - RIVNUT BODY TOP RAIL SPIGOT LOW X" add sketch "SKETCH - RIVNUT BODY TOP RAIL SPIGOT LOW X" against normal blind 10.16 separate body makes body 21 in component "838003 HARDWARE - RIVET NUT - M6 - SHEREX CAH3-610-4.2"
combine "COMBINE - RIVNUT TOP RAIL SPIGOT LOW X" operation add target body 20 tool bodies 21 in component "838003 HARDWARE - RIVET NUT - M6 - SHEREX CAH3-610-4.2"
ref_plane "WorkPlane1" through (0, 0, 1231.63) normal (0, 0, 1) x (1, 0, 0) in component "831001 HARDWARE - LOCATING SPIGOT - M6 X Ø8 - STAINLESS"
sketch "SKETCH - SPIGOT PIN TOP RAIL SPIGOT LOW X" plane through (0, 0, 1231.63) normal (0, 0, 1) x (1, 0, 0) in component "831001 HARDWARE - LOCATING SPIGOT - M6 X Ø8 - STAINLESS"
  circle A0 centre (-1101.74, 824) radius 4
  dimension "d993" = 1101.74
  dimension "d994" = 824
  dimension "d995" = 8
  measures "d993" horizontal distance of origin A0.centre
  measures "d994" vertical distance of origin A0.centre
  measures "d995" diameter of A0
extrude "EXTRUDE - SPIGOT PIN TOP RAIL SPIGOT LOW X" add sketch "SKETCH - SPIGOT PIN TOP RAIL SPIGOT LOW X" along normal blind 7.24 separate body makes body 22 in component "831001 HARDWARE - LOCATING SPIGOT - M6 X Ø8 - STAINLESS"
ref_plane "WorkPlane2" through (0, 0, 1231.63) normal (0, 0, 1) x (1, 0, 0) in component "831001 HARDWARE - LOCATING SPIGOT - M6 X Ø8 - STAINLESS"
sketch "SKETCH - SPIGOT THREAD TOP RAIL SPIGOT LOW X" plane through (0, 0, 1231.63) normal (0, 0, 1) x (1, 0, 0) in component "831001 HARDWARE - LOCATING SPIGOT - M6 X Ø8 - STAINLESS"
  circle A0 centre (-1101.74, 824) radius 3
  dimension "d1000" = 1101.74
  dimension "d1001" = 824
  dimension "d1002" = 6
  measures "d1000" horizontal distance of origin A0.centre
  measures "d1001" vertical distance of origin A0.centre
  measures "d1002" diameter of A0
extrude "EXTRUDE - SPIGOT THREAD TOP RAIL SPIGOT LOW X" add sketch "SKETCH - SPIGOT THREAD TOP RAIL SPIGOT LOW X" against normal blind 10 separate body makes body 23 in component "831001 HARDWARE - LOCATING SPIGOT - M6 X Ø8 - STAINLESS"
combine "COMBINE - SPIGOT TOP RAIL SPIGOT LOW X" operation add target body 22 tool bodies 23 in component "831001 HARDWARE - LOCATING SPIGOT - M6 X Ø8 - STAINLESS"
ref_plane "WorkPlane5" through (0, 0, 1230.87) normal (0, 0, 1) x (1, 0, 0) in component "838003 HARDWARE - RIVET NUT - M6 - SHEREX CAH3-610-4.2"
sketch "SKETCH - RIVNUT HEAD TOP RAIL SPIGOT HIGH X" plane through (0, 0, 1230.87) normal (0, 0, 1) x (1, 0, 0) in component "838003 HARDWARE - RIVET NUT - M6 - SHEREX CAH3-610-4.2"
  circle A0 centre (-102.75, 824) radius 6.48
  circle A1 centre (-102.75, 824) radius 3
  dimension "d1009" = 102.75
  dimension "d1010" = 824
  dimension "d1011" = 12.96
  dimension "d1012" = 6
  measures "d1009" horizontal distance of origin A0.centre
  measures "d1010" vertical distance of origin A0.centre
  measures "d1011" diameter of A0
  measures "d1012" diameter of A1
extrude "EXTRUDE - RIVNUT HEAD TOP RAIL SPIGOT HIGH X" add sketch "SKETCH - RIVNUT HEAD TOP RAIL SPIGOT HIGH X" along normal blind 0.76 separate body makes body 24 in component "838003 HARDWARE - RIVET NUT - M6 - SHEREX CAH3-610-4.2"
ref_plane "WorkPlane6" through (0, 0, 1230.87) normal (0, 0, 1) x (1, 0, 0) in component "838003 HARDWARE - RIVET NUT - M6 - SHEREX CAH3-610-4.2"
sketch "SKETCH - RIVNUT BODY TOP RAIL SPIGOT HIGH X" plane through (0, 0, 1230.87) normal (0, 0, 1) x (1, 0, 0) in component "838003 HARDWARE - RIVET NUT - M6 - SHEREX CAH3-610-4.2"
  circle A0 centre (-102.75, 824) radius 4.75
  circle A1 centre (-102.75, 824) radius 3
  dimension "d1017" = 102.75
  dimension "d1018" = 824
  dimension "d1019" = 9.5
  dimension "d1020" = 6
  measures "d1017" horizontal distance of origin A0.centre
  measures "d1018" vertical distance of origin A0.centre
  measures "d1019" diameter of A0
  measures "d1020" diameter of A1
extrude "EXTRUDE - RIVNUT BODY TOP RAIL SPIGOT HIGH X" add sketch "SKETCH - RIVNUT BODY TOP RAIL SPIGOT HIGH X" against normal blind 10.16 separate body makes body 25 in component "838003 HARDWARE - RIVET NUT - M6 - SHEREX CAH3-610-4.2"
combine "COMBINE - RIVNUT TOP RAIL SPIGOT HIGH X" operation add target body 24 tool bodies 25 in component "838003 HARDWARE - RIVET NUT - M6 - SHEREX CAH3-610-4.2"
ref_plane "WorkPlane3" through (0, 0, 1231.63) normal (0, 0, 1) x (1, 0, 0) in component "831001 HARDWARE - LOCATING SPIGOT - M6 X Ø8 - STAINLESS"
sketch "SKETCH - SPIGOT PIN TOP RAIL SPIGOT HIGH X" plane through (0, 0, 1231.63) normal (0, 0, 1) x (1, 0, 0) in component "831001 HARDWARE - LOCATING SPIGOT - M6 X Ø8 - STAINLESS"
  circle A0 centre (-102.75, 824) radius 4
  dimension "d1027" = 102.75
  dimension "d1028" = 824
  dimension "d1029" = 8
  measures "d1027" horizontal distance of origin A0.centre
  measures "d1028" vertical distance of origin A0.centre
  measures "d1029" diameter of A0
extrude "EXTRUDE - SPIGOT PIN TOP RAIL SPIGOT HIGH X" add sketch "SKETCH - SPIGOT PIN TOP RAIL SPIGOT HIGH X" along normal blind 7.24 separate body makes body 26 in component "831001 HARDWARE - LOCATING SPIGOT - M6 X Ø8 - STAINLESS"
ref_plane "WorkPlane4" through (0, 0, 1231.63) normal (0, 0, 1) x (1, 0, 0) in component "831001 HARDWARE - LOCATING SPIGOT - M6 X Ø8 - STAINLESS"
sketch "SKETCH - SPIGOT THREAD TOP RAIL SPIGOT HIGH X" plane through (0, 0, 1231.63) normal (0, 0, 1) x (1, 0, 0) in component "831001 HARDWARE - LOCATING SPIGOT - M6 X Ø8 - STAINLESS"
  circle A0 centre (-102.75, 824) radius 3
  dimension "d1034" = 102.75
  dimension "d1035" = 824
  dimension "d1036" = 6
  measures "d1034" horizontal distance of origin A0.centre
  measures "d1035" vertical distance of origin A0.centre
  measures "d1036" diameter of A0
extrude "EXTRUDE - SPIGOT THREAD TOP RAIL SPIGOT HIGH X" add sketch "SKETCH - SPIGOT THREAD TOP RAIL SPIGOT HIGH X" against normal blind 10 separate body makes body 27 in component "831001 HARDWARE - LOCATING SPIGOT - M6 X Ø8 - STAINLESS"
combine "COMBINE - SPIGOT TOP RAIL SPIGOT HIGH X" operation add target body 26 tool bodies 27 in component "831001 HARDWARE - LOCATING SPIGOT - M6 X Ø8 - STAINLESS"
component "211201 WALL - PANEL FRAME - BACK LOWER - B1" placed x (1, 0, 0) y (0, 1, 0) z (0, 0, 1) at (0, 0, 0)
component "211401 WALL - SKIN - BACK LOWER - B1" placed x (1, 0, 0) y (0, 1, 0) z (0, 0, 1) at (0, 0, 0)
component "211601 WALL - CAVITY FILL - BACK LOWER - B1" placed x (1, 0, 0) y (0, 1, 0) z (0, 0, 1) at (0, 0, 0)
component "831002 HARDWARE - STOP WASHER - Ø10.5 X Ø20 X 1.5 - AL" placed x (1, 0, 0) y (0, 1, 0) z (0, 0, 1) at (0, 0, 0)
component "838003 HARDWARE - RIVET NUT - M6 - SHEREX CAH3-610-4.2" placed x (1, 0, 0) y (0, 1, 0) z (0, 0, 1) at (0, 0, 0)
component "831001 HARDWARE - LOCATING SPIGOT - M6 X Ø8 - STAINLESS" placed x (1, 0, 0) y (0, 1, 0) z (0, 0, 1) at (0, 0, 0)
equation "pod_w_Ref = 2500 mm" comment "DECIDED: D-01; conventions s4 (X = +-1250)"
equation "pod_d_Ref = 1700 mm" comment "DECIDED: D-01; conventions s4 (Y = +-850)"
equation "pod_h_Ref = 2400 mm" comment "DECIDED: D-21 (room floor to roof skin top)"
equation "glide_h_Ref = 10 mm" comment "ASSUMPTION: layout study inputs.py glide_h"
equation "band_h_Ref = 100 mm" comment "SOURCE: layout study B1 list B-BAND 100x40; inputs.py base_h"
equation "outer_t_Ref = skin_t_Ref + bond_t_Ref + frame_t_Ref" comment "DECIDED: PM ruling 2026-10-31: ACP 3 + bond line 3 + frame 40, walls and ceiling (was 43)"
equation "cav_gap_Ref = 4 mm" comment "DECIDED: D-16, D-42: the gap between the outer panel and the lining cassette in the wall and ceiling stack"
equation "cass_t_Ref = 34 mm" comment "SOURCE: layout study B1 final list L-CASS 34 (tray + 25 gap + felt 9)"
equation "stack_t_Ref = outer_t_Ref + cav_gap_Ref + cass_t_Ref" comment "CALCULATION: D-16, D-42 stack, walls and ceiling: outer panel + cavity gap + cassette (PM ruling 2026-10-31 on outer_t)"
equation "lin_gap_Ref = 4 mm" comment "ASSUMPTION: PM ruling pass C: gap above the upper side linings so they stay floating (= the 4 mm stack gap)"
equation "seam_gap_Ref = 2.26 mm" comment "DECIDED: PM ruling 2026-10-31 (Mechanical Checker F-001, F-005): the Joints Engineer's 2.26 mm at all nine site seam types, set by a metal stop (1.5 stop washer + 0.76 rivnut head; joints register section 2.8)"
equation "wall_z0_Ref = glide_h_Ref + band_h_Ref" comment "CALCULATION: base band top: glides + band"
equation "panel_z0_Ref = wall_z0_Ref + seam_gap_Ref" comment "CALCULATION: walls stand one seam_gap above the band top (joints register 2.8, IF-01)"
equation "back_oh_Ref = pod_h_Ref - outer_t_Ref - seam_gap_Ref - panel_z0_Ref" comment "CALCULATION: PM ruling 2026-10-31 (pass D, F-004): the back outer frames run up to the ceiling frame (pod_h - outer_t), less the seam_gap under it, closing the slot at the back top edge"
equation "back_ph_Ref = ( back_oh_Ref - seam_gap_Ref ) / 2" comment "CALCULATION: D-23: 4 sheets on the back, two equal rows with one seam_gap between them (joints register 2.8); the lower back linings match the lower row, as on the side walls"
equation "half_pw_Ref = ( pod_w_Ref - 2 * outer_t_Ref - 3 * seam_gap_Ref ) / 2" comment "CALCULATION: SKIN width of each back and ceiling panel: two skins and three seam_gap seams between the side frames (F-001, joints register 2.8)"
equation "n_base_bolt_Ref = 4" comment "DECIDED: PM ruling 2026-10-31, J-BASE-01: bolts per panel along the band, evenly spaced"
equation "skin_t_Ref = 3 mm" comment "DECIDED: ACP skin, walls and ceiling (D-16; PM ruling 2026-10-31 on outer_t)"
equation "bond_t_Ref = 3 mm" comment "DECIDED: bond line between the ACP and the frame (PM ruling 2026-10-31 on outer_t)"
equation "frame_t_Ref = 40 mm" comment "DECIDED: aluminium frame tube depth, walls and ceiling (PM ruling 2026-10-31 on outer_t)"
equation "close_gap_Ref = 5.5 mm" comment "DECIDED: PM ruling 2026-10-31 (joints register, F-011/F-012): frame gap at the closing seams B1-B2, B3-B4 and C1-C2, which have no hard stop (slotted holes, thicker gasket)"
equation "half_fw_Ref = ( pod_w_Ref - 2 * outer_t_Ref - 2 * seam_gap_Ref - close_gap_Ref ) / 2" comment "CALCULATION: FRAME width of each back and ceiling panel: the skins overhang their frames by half_pw - half_fw at the closing seam (PM ruling 2026-10-31)"
equation "bolt_edge_inset_Ref = 220 mm" comment "DECIDED: PM ruling 2026-10-31: on every bolted edge the end bolts sit this far in from each panel end, the rest evenly spaced"
equation "spigot_inset_Ref = 100 mm" comment "DECIDED: PM ruling 2026-10-31: locating spigots this far in from each panel end (round hole at one end, slot at the other)"
equation "pod_w = pod_w_Ref" comment "LINKED: pod_w_Ref, derived from 100000_P04_POD-SKELETON_CAD v4 (skeleton is the single source)"
equation "pod_d = pod_d_Ref" comment "LINKED: pod_d_Ref, derived from 100000_P04_POD-SKELETON_CAD v4 (skeleton is the single source)"
equation "pod_h = pod_h_Ref" comment "LINKED: pod_h_Ref, derived from 100000_P04_POD-SKELETON_CAD v4 (skeleton is the single source)"
equation "panel_z0 = panel_z0_Ref" comment "LINKED: panel_z0_Ref, derived from 100000_P04_POD-SKELETON_CAD v4 (skeleton is the single source)"
equation "back_ph = back_ph_Ref" comment "LINKED: back_ph_Ref, derived from 100000_P04_POD-SKELETON_CAD v4 (skeleton is the single source)"
equation "back_oh = back_oh_Ref" comment "LINKED: back_oh_Ref, derived from 100000_P04_POD-SKELETON_CAD v4 (skeleton is the single source)"
equation "half_pw = half_pw_Ref" comment "LINKED: half_pw_Ref, derived from 100000_P04_POD-SKELETON_CAD v4 (skeleton is the single source)"
equation "half_fw = half_fw_Ref" comment "LINKED: half_fw_Ref, derived from 100000_P04_POD-SKELETON_CAD v4 (skeleton is the single source)"
equation "close_gap = close_gap_Ref" comment "LINKED: close_gap_Ref, derived from 100000_P04_POD-SKELETON_CAD v4 (skeleton is the single source)"
equation "stack_t = stack_t_Ref" comment "LINKED: stack_t_Ref, derived from 100000_P04_POD-SKELETON_CAD v4 (skeleton is the single source)"
equation "outer_t = outer_t_Ref" comment "LINKED: outer_t_Ref, derived from 100000_P04_POD-SKELETON_CAD v4 (skeleton is the single source)"
equation "cass_t = cass_t_Ref" comment "LINKED: cass_t_Ref, derived from 100000_P04_POD-SKELETON_CAD v4 (skeleton is the single source)"
equation "lin_gap = lin_gap_Ref" comment "LINKED: lin_gap_Ref, derived from 100000_P04_POD-SKELETON_CAD v4 (skeleton is the single source)"
equation "seam_gap = seam_gap_Ref" comment "LINKED: seam_gap_Ref, derived from 100000_P04_POD-SKELETON_CAD v4 (skeleton is the single source)"
equation "skin_t = skin_t_Ref" comment "LINKED: skin_t_Ref, derived from 100000_P04_POD-SKELETON_CAD v4 (skeleton is the single source)"
equation "bond_t = bond_t_Ref" comment "LINKED: bond_t_Ref, derived from 100000_P04_POD-SKELETON_CAD v4 (skeleton is the single source)"
equation "bolt_edge_inset = bolt_edge_inset_Ref" comment "LINKED: bolt_edge_inset_Ref, derived from 100000_P04_POD-SKELETON_CAD v4 (skeleton is the single source)"
equation "spigot_inset = spigot_inset_Ref" comment "LINKED: spigot_inset_Ref, derived from 100000_P04_POD-SKELETON_CAD v4 (skeleton is the single source)"